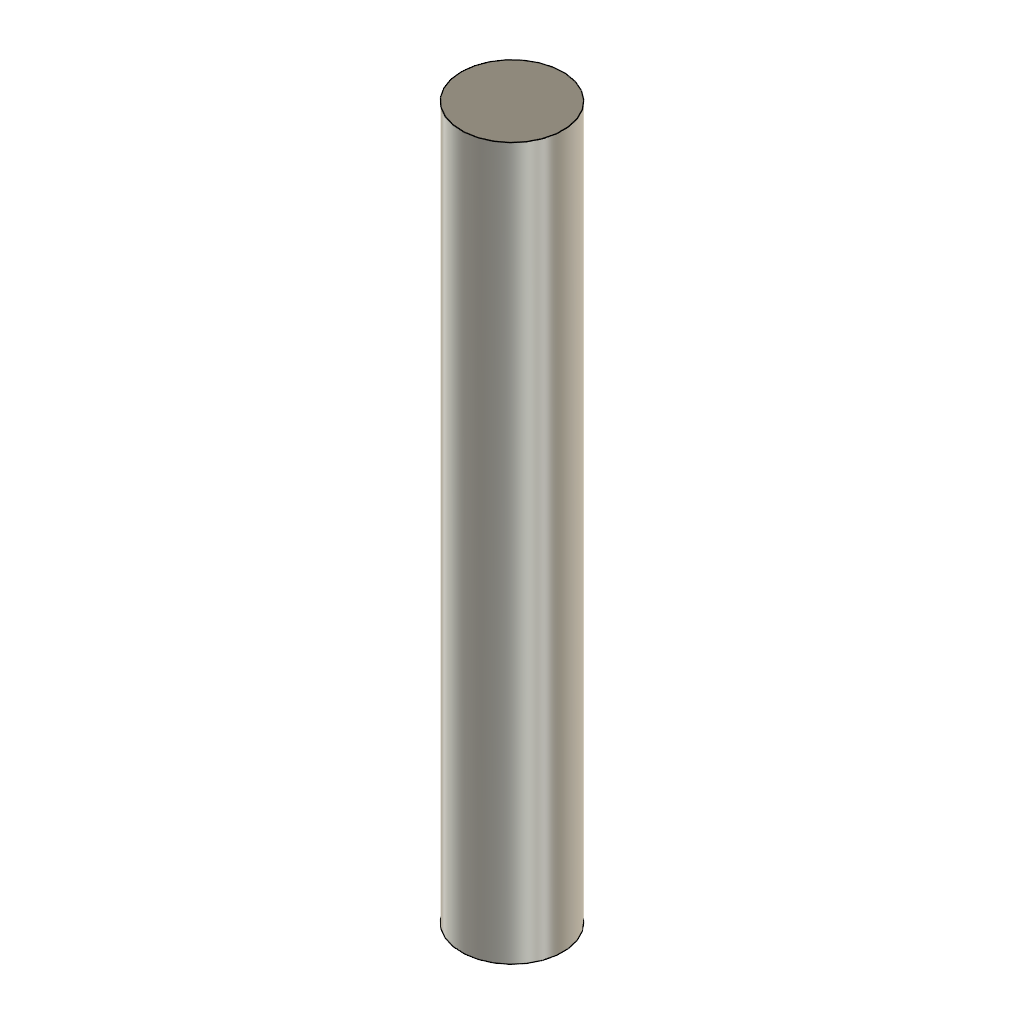
FLASH Core XY (Autodesk Fusion 360 archive; units mm, degrees)
design "Pulley Pin"
part number: 2026-10-21-10-58-50-393
Autodesk Fusion 360 part; units mm, degrees
sketch "Sketch1" plane through (0, 0, 0) normal (0, 0, 1) x (1, 0, 0)
  circle A0 centre (0, 0) radius 2.5
  dimension "d1" = 5
  constraint coincident A0.centre origin
  measures "d1" diameter of A0
extrude "Extrude1" add sketch "Sketch1" along normal mid plane 35

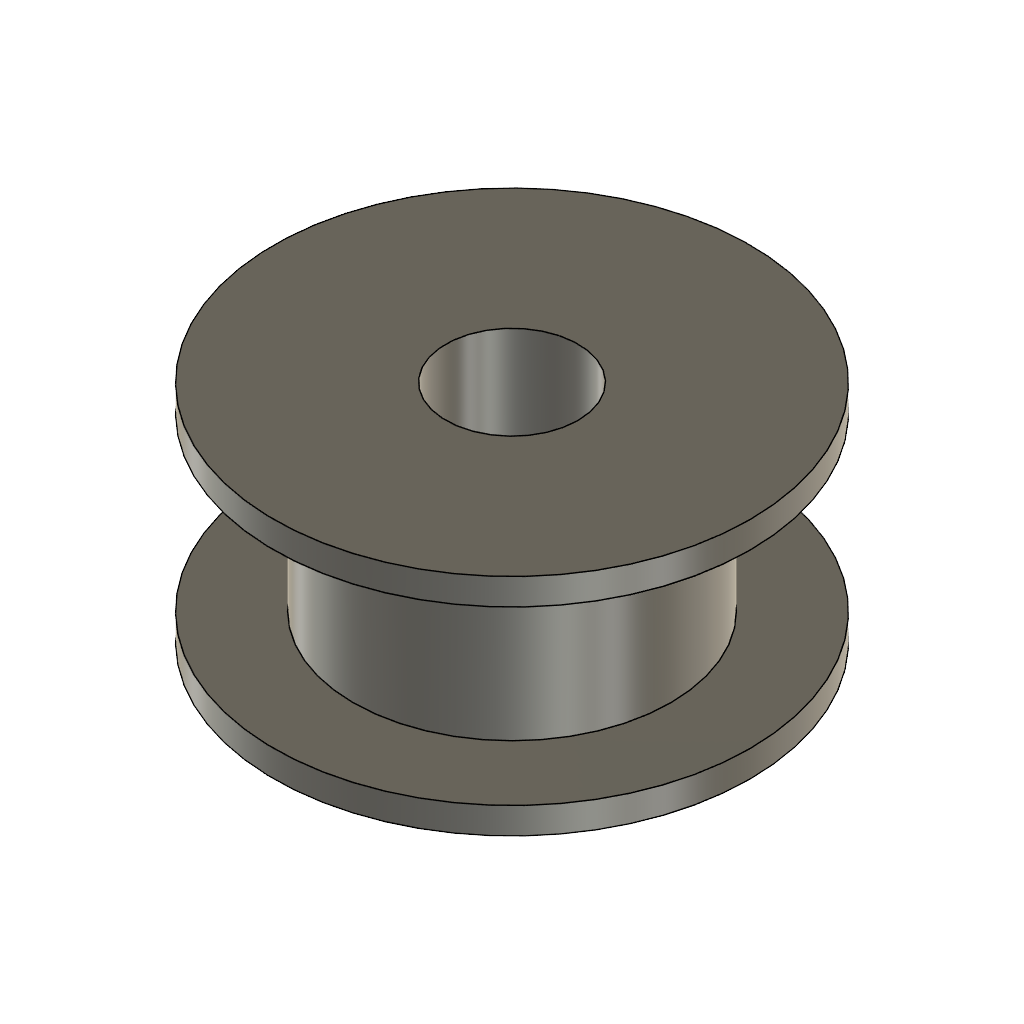
design "GT2 Idler Pulley 6mm"
part number: 2026-10-15-13-51-56-063
Autodesk Fusion 360 part; units mm, degrees
sketch "Sketch1" plane through (0, 0, 0) normal (0, 0, 1) x (1, 0, 0)
  circle A0 centre (0, 0) radius 6
  dimension "d1" = 12
  constraint coincident A0.centre origin
  measures "d1" diameter of A0
extrude "Extrude1" add sketch "Sketch1" along normal mid plane 6.5 makes body 1
sketch "Sketch2" plane through (0, 0, 3.25) normal (0, 0, 1) x (-1, 0, 0)
  circle A0 centre (0, 0) radius 6
  circle A1 centre (0, 0) radius 9
  dimension "d4" = 18
  constraint coincident A0.centre A1.centre
  measures "d4" diameter of A1
extrude "Extrude2" add sketch "Sketch2" along normal blind 1 contours A0 | A1 bodies 1
mirror "Mirror1" about plane through (0, 0, 0) normal (0, 0, 1) of "Extrude2"
sketch "Sketch3" plane through (0, 0, 4.25) normal (0, 0, 1) x (-1, 0, 0)
  circle A0 centre (0, 0) radius 9
hole "Hole1" at (0, 0, 4.25) direction (0, 0, -1) diameter 5 end through all bodies 1
sketch "Sketch4" plane through (0, 0, 0) normal (0, 0, 1) x (1, 0, 0)
  circle A0 centre (0, 0) radius 10
  dimension "d11" = 20
  constraint coincident A0.centre origin
  measures "d11" diameter of A0
extrude "Extrude3" add sketch "Sketch4" along normal mid plane 9.5 separate body makes body 2
hidden bodies 2
named bodies: "Pulley", "Pocket"

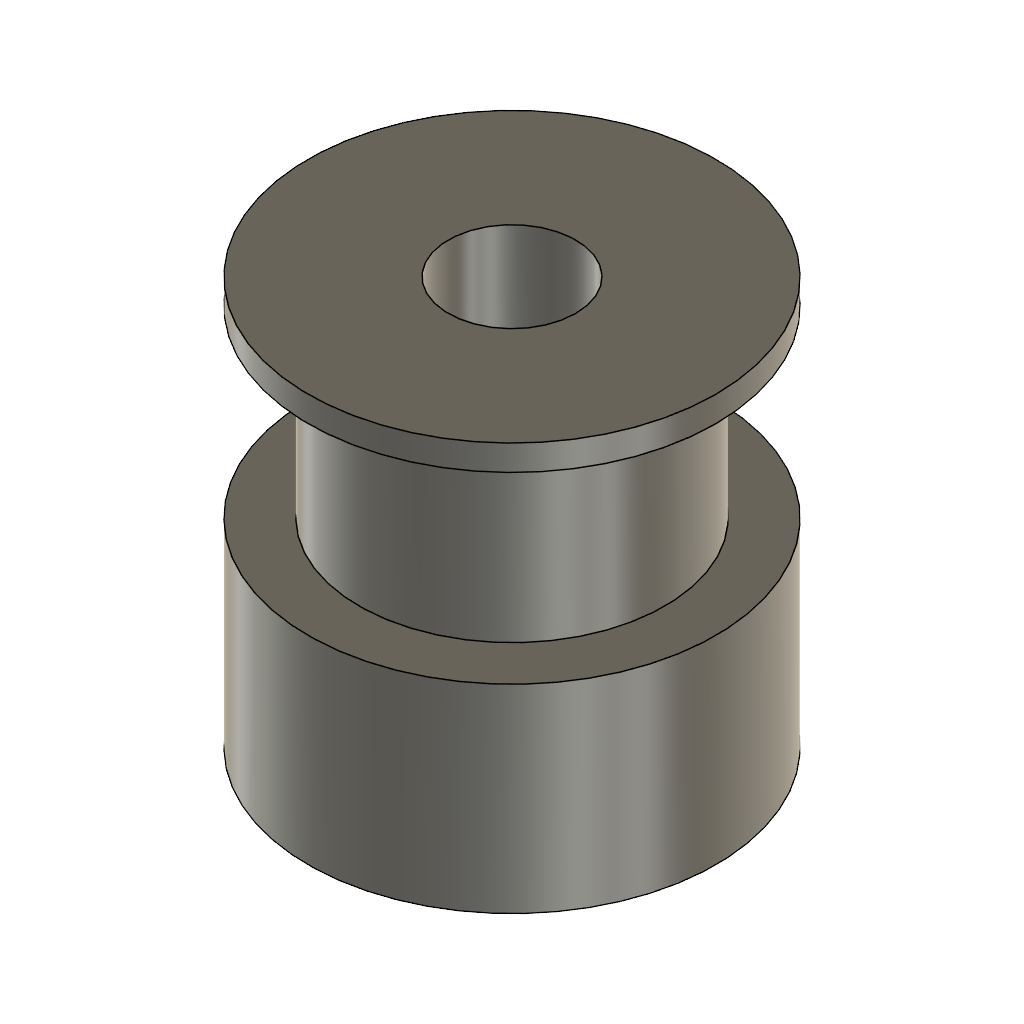
design "GT Drive Pulley 6mm"
part number: 2026-10-15-14-07-30-111
Autodesk Fusion 360 part; units mm, degrees
sketch "Sketch1" plane through (0, 0, 0) normal (0, 0, 1) x (1, 0, 0)
  circle A0 centre (0, 0) radius 6
  dimension "d1" = 12
  constraint coincident A0.centre origin
  measures "d1" diameter of A0
extrude "Extrude1" add sketch "Sketch1" along normal mid plane 7.2 makes body 1
sketch "Sketch2" plane through (0, 0, 3.6) normal (0, 0, 1) x (-1, 0, 0)
  circle A0 centre (0, 0) radius 6
  circle A1 centre (0, 0) radius 8
  dimension "d4" = 16
  constraint coincident A0.centre A1.centre
  measures "d4" diameter of A1
extrude "Extrude2" add sketch "Sketch2" along normal blind 1 contours A0 | A1 bodies 1
sketch "Sketch3" plane through (0, 0, -3.6) normal (0, 0, -1) x (1, 0, 0)
  circle A0 centre (0, 0) radius 6
  circle A1 centre (0, 0) radius 8
  dimension "d7" = 16
  constraint coincident A0.centre A1.centre
  measures "d7" diameter of A1
extrude "Extrude3" add sketch "Sketch3" along normal blind 7.8 contours A0 | A1 bodies 1
sketch "Sketch4" plane through (0, 0, 4.6) normal (0, 0, 1) x (-1, 0, 0)
  circle A0 centre (0, 0) radius 8
hole "Hole1" at (0, 0, 4.6) direction (0, 0, -1) diameter 5 end through all bodies 1
sketch "Sketch5" plane through (0, 0, 0) normal (0, 0, 1) x (1, 0, 0)
  circle A0 centre (0, 0) radius 9
  dimension "d12" = 18
  constraint coincident A0.centre origin
  measures "d12" diameter of A0
extrude "Extrude4" add sketch "Sketch5" along normal up to surface (5.6 mm away) and the other way up to surface (12.4 mm away) separate body makes body 2
hidden bodies 2
named bodies: "Pulley", "Pocket"

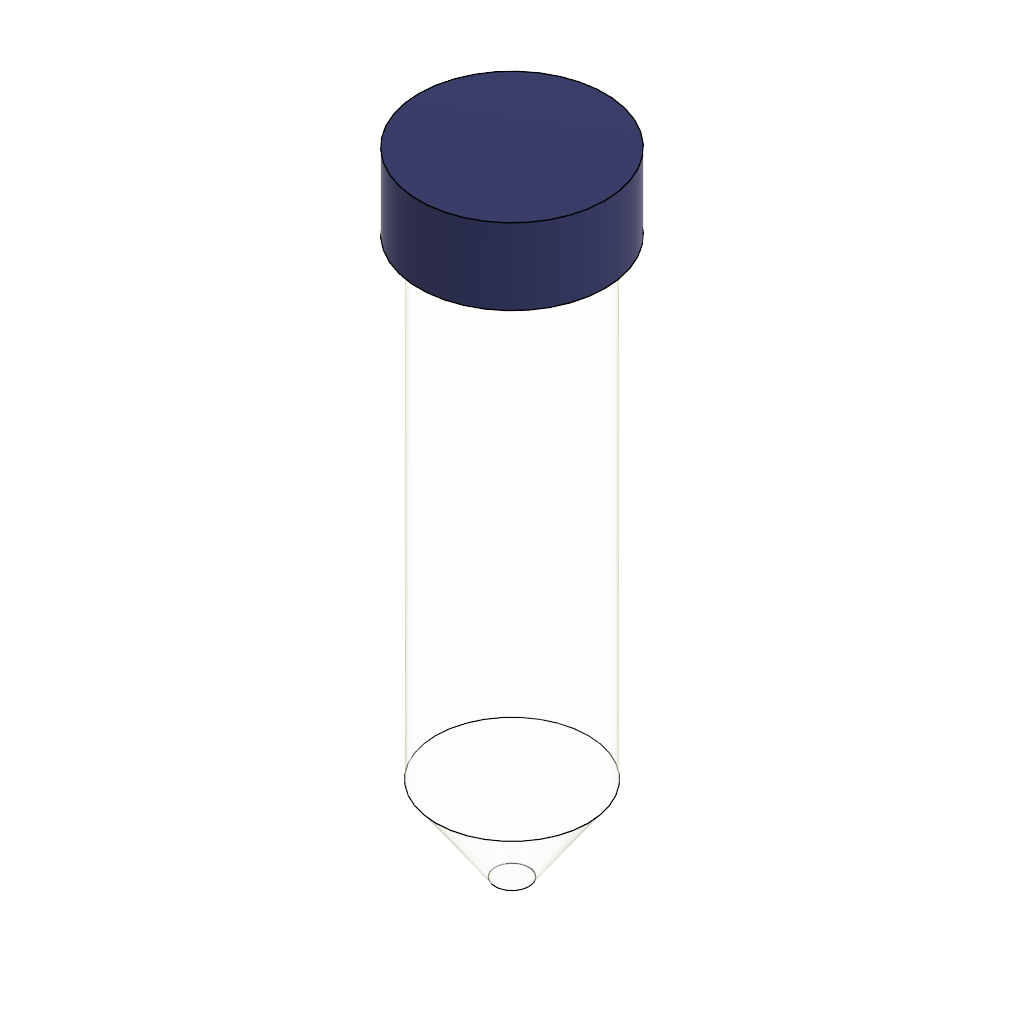
design "TestTube50mL"
Autodesk Fusion 360 part; units mm, degrees
sketch "Sketch1" plane through (0, 0, 0) normal (0, 0, 1) x (1, 0, 0)
  circle A0 centre (0, 0) radius 14.2875
  circle A1 centre (-150, 75) radius 3.1006
  dimension "d1" = 28.575
  constraint coincident A0.centre origin
  measures "d1" diameter of A0
extrude "Extrude1" add sketch "Sketch1" along normal blind 118.745 contours A0 makes body 1
sketch "Sketch2" plane through (0, 0, 118.745) normal (0, 0, 1) x (-1, 0, 0)
  circle A0 centre (0, 0) radius 14.2875
  circle A1 centre (0, 0) radius 17.4625
  dimension "d4" = 34.925
  constraint coincident A0.centre A1.centre
  measures "d4" diameter of A1
extrude "Extrude2" add sketch "Sketch2" against normal blind 14.2875 bodies 1
chamfer "Chamfer1" distance 15.875 distance2 11.1125 1 edges at (-13.3206, -5.1666, 0) measured on face at (14.2165, 1.4226, 69.6383) tangent chain off on bodies 1
ref_plane "WorkPlane1" through (0, 0, 20.6375) normal (0, 0, 1) x (1, 0, 0)
sketch "Sketch3" plane through (0, 0, 20.6375) normal (0, 0, 1) x (1, 0, 0)
  circle A0 centre (0, 0) radius 14.2875
  circle A1 centre (0, 0) radius 14.2875
split "Split1" by plane through (0, 0, 104.4575) normal (0, 0, -1) bodies 1 makes body 2 at (14.2165, 1.4226, 74.93)
equation "d5 = ( -9 / 16 ) * 1 in"
equation "d7 = ( 5 / 8 ) * 1 in"
equation "d8 = ( ( 1.125 - 0.25 ) / 2 ) * 1 in"
equation "d9 = ( 13 / 16 ) * 1 in"

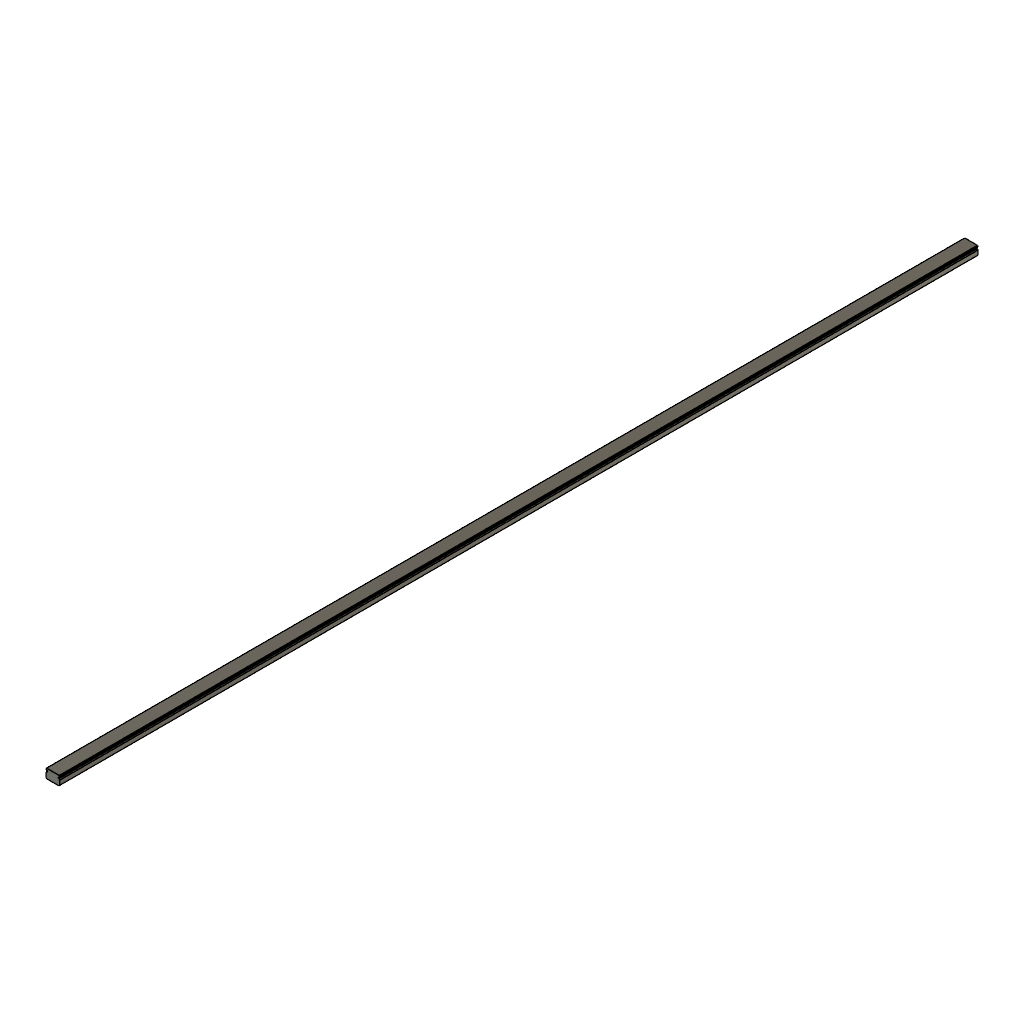
design "MGN15 Rail"
part number: 2026-10-15-13-23-19-019
Autodesk Fusion 360 part; units mm, degrees
sketch "Sketch1" plane through (0, 0, 0) normal (0, 1, 0) x (1, 0, 0)
  line L0 (-7.5, 0) -> (7.5, 0)
  line L1 (7.5, 0) -> (7.5, 10)
  line L2 (7.5, 10) -> (-7.5, 10)
  line L3 (-7.5, 10) -> (-7.5, 0)
  line L4 (-7.5, 0) -> (7.5, 10) construction
  line L5 (7.5, 0) -> (-7.5, 10) construction
  point P0 (0, 5)
  dimension "d1" = 15
  dimension "d2" = 10
  constraint horizontal L0
  constraint perpendicular L0 L1
  constraint parallel L0 L2
  constraint parallel L1 L3
  constraint coincident L4 P0
  constraint coincident L5 P0
  constraint vertical origin P0
  constraint coincident origin L0
  measures "d1" distance of L1.end L2.end
  measures "d2" distance of L0.start L2.end
extrude "Extrude1" add sketch "Sketch1" along normal mid plane 1000
sketch "Sketch2" plane through (0, 0, 0) normal (0, 1, 0) x (1, 0, 0)
  line L0 (-7.5, 0) -> (-7.5, 10)
  line L1 (-7.5, 10) -> (7.5, 10)
  line L2 (7.5, 10) -> (7.5, 0)
  line L3 (7.5, 0) -> (-7.5, 0)
  line L4 (7.5, 2.2) -> (5.8, 2.2)
  line L5 (5.8, 2.2) -> (5.8, 3.2)
  line L6 (5.8, 3.2) -> (7.5, 3.2)
  line L7 (7.5, 3.2) -> (7.5, 2.2)
  point P0 (5.8, 2.7)
  dimension "d5" = 7.3
  dimension "d6" = 1.7
  dimension "d7" = 1
  constraint horizontal L4
  constraint vertical L5
  constraint horizontal L6
  constraint vertical L7
  constraint coincident L2 L4.start
  constraint midpoint L5 P0
  measures "d5" distance of L1 P0
  measures "d6" distance of L5.end L6.end
  measures "d7" distance of L4.end L5.end
extrude "Extrude2" cut sketch "Sketch2" along normal through all and the other way through all contours L2 L4 L5 L6 L7
mirror "Mirror1" about plane through (0, 0, 0) normal (1, 0, 0) of "Extrude2"
chamfer "Chamfer1" distance 0.5 angle 45 2 edges at (-7.5, 0, 0) (7.5, 0, 0) tangent chain off
chamfer "Chamfer2" distance 0.9 angle 45 2 edges at (-7.5, 0, -10) (7.5, 0, -10) tangent chain off
chamfer "Chamfer3" distance 0.9 angle 45 4 edges at (-7.5, 0, -3.2) (-7.5, 0, -2.2) (7.5, 0, -3.2) (7.5, 0, -2.2) tangent chain off
fillet "Fillet1" radius 0.3 4 edges at (5.8, 0, -2.2) (5.8, 0, -3.2) (-5.8, 0, -2.2) (-5.8, 0, -3.2)

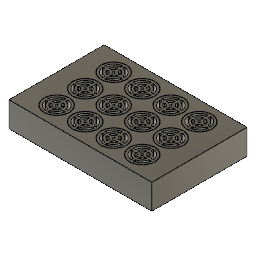
design "WellPlate3x4"
Autodesk Fusion 360 part; units mm, degrees
sketch "Sketch1" plane through (0, 0, 0) normal (0, 0, 1) x (1, 0, 0)
  line L0 (-63.75, 42.5) -> (63.75, 42.5)
  line L1 (63.75, 42.5) -> (63.75, -42.5)
  line L2 (63.75, -42.5) -> (-63.75, -42.5)
  line L3 (-63.75, -42.5) -> (-63.75, 42.5)
  line L4 (-63.75, 42.5) -> (63.75, -42.5) construction
  line L5 (63.75, 42.5) -> (-63.75, -42.5) construction
  dimension "d1" = 85
  dimension "d2" = 127.5
  constraint horizontal L0
  constraint perpendicular L0 L1
  constraint parallel L0 L2
  constraint parallel L1 L3
  constraint coincident L4 origin
  constraint coincident L5 origin
  measures "d1" distance of L0.start L2.end
  measures "d2" distance of L0.start L0.end
extrude "Extrude1" add sketch "Sketch1" along normal blind 22.5 makes body 1
sketch "Sketch2" plane through (0, 0, 22.5) normal (0, 0, 1) x (-1, 0, 0)
  line L0 (63.75, 42.5) -> (-63.75, 42.5)
  line L1 (-63.75, 42.5) -> (-63.75, -42.5)
  line L2 (-63.75, -42.5) -> (63.75, -42.5)
  line L3 (63.75, -42.5) -> (63.75, 42.5)
  circle A0 centre (38.1, -25.4) radius 11.25
  dimension "d5" = 22.5
  dimension "d6" = 38.1
  dimension "d7" = 25.4
  measures "d5" diameter of A0
  measures "d6" horizontal distance of origin A0.centre
  measures "d7" vertical distance of origin A0.centre
extrude "Extrude2" cut sketch "Sketch2" against normal through all contours A0 bodies 1
pattern_linear "R-Pattern1" count 4 spacing 25.4 along (1, 0, 0) count 3 spacing 25.4 along (0, -1, 0) of "Extrude2"
sketch "Sketch3" plane through (0, 0, 22.5) normal (0, 0, 1) x (-1, 0, 0)
  circle A0 centre (-38.1, 25.4) radius 11.25
  circle A1 centre (-12.7, 25.4) radius 11.25
  circle A2 centre (12.7, 25.4) radius 11.25
  circle A3 centre (38.1, 25.4) radius 11.25
  circle A4 centre (-38.1, 0) radius 11.25
  circle A5 centre (-12.7, 0) radius 11.25
  circle A6 centre (12.7, 0) radius 11.25
  circle A7 centre (38.1, 0) radius 11.25
  circle A8 centre (-38.1, -25.4) radius 11.25
  circle A9 centre (-12.7, -25.4) radius 11.25
  circle A10 centre (12.7, -25.4) radius 11.25
  circle A11 centre (38.1, -25.4) radius 11.25
  line L0 (63.75, 42.5) -> (-63.75, 42.5)
  line L1 (-63.75, 42.5) -> (-63.75, -42.5)
  line L2 (-63.75, -42.5) -> (63.75, -42.5)
  line L3 (63.75, -42.5) -> (63.75, 42.5)
  circle A12 centre (38.1, -25.4) radius 11.25
  circle A13 centre (38.1, -25.4) radius 1
  circle A14 centre (38.1, -25.4) radius 5
  circle A15 centre (38.1, -25.4) radius 7
  circle A16 centre (38.1, -25.4) radius 9
  circle A17 centre (38.1, -25.4) radius 3
  line L4 (26.85, -26.4) -> (49.35, -26.4)
  line L5 (49.35, -26.4) -> (49.35, -24.4)
  line L6 (49.35, -24.4) -> (26.85, -24.4)
  line L7 (26.85, -24.4) -> (26.85, -26.4)
  line L8 (26.85, -26.4) -> (49.35, -24.4) construction
  line L9 (49.35, -26.4) -> (26.85, -24.4) construction
  line L10 (37.1, -36.65) -> (39.1, -36.65)
  line L11 (39.1, -36.65) -> (39.1, -14.15)
  line L12 (39.1, -14.15) -> (37.1, -14.15)
  line L13 (37.1, -14.15) -> (37.1, -36.65)
  line L14 (37.1, -36.65) -> (39.1, -14.15) construction
  line L15 (39.1, -36.65) -> (37.1, -14.15) construction
  circle A18 centre (38.1, -25.4) radius 11
  point P0 (38.1, -25.4)
  point P1 (38.1, -25.4)
  dimension "d14" = 2
  dimension "d15" = 2
  dimension "d16" = 2
  dimension "d17" = 2
  dimension "d18" = 2
  dimension "d19" = 2
  dimension "d27" = 2
  dimension "d28" = 2
  constraint concentric A12 A13
  constraint concentric A12 A14
  constraint concentric A12 A15
  constraint concentric A14 A16
  constraint concentric A12 A17
  constraint horizontal L4
  constraint perpendicular L4 L5
  constraint parallel L4 L6
  constraint parallel L5 L7
  constraint coincident L8 P1
  constraint coincident L9 P1
  constraint coincident P1 P0
  constraint horizontal L10
  constraint perpendicular L10 L11
  constraint parallel L10 L12
  constraint parallel L11 L13
  constraint coincident L14 P1
  constraint coincident L15 P1
  constraint tangent A11 L7
  constraint tangent A12 L10
  constraint concentric A11 A18
  measures "d14" distance of A15 A16
  measures "d15" distance of A14 A15
  measures "d16" distance of A14 A17
  measures "d17" distance of A13 A17
  measures "d18" distance of L10.start L10.end
  measures "d19" distance of L4.end L5.end
  measures "d27" diameter of A13
  measures "d28" distance of A16 A18
extrude "Extrude3" add sketch "Sketch3" against normal blind 8 separate body contours A11 A12 L4 L6 A18 | A11 A12 L11 L13 A18 | A16 L4 L6 A18 | A16 L6 L11 A18 | A11 A12 L11 L13 A18 | A16 L4 L11 A18 | A16 L11 L13 A18 | A15 A16 L4 L6 | A16 L11 L13 A18 | A15 A16 L11 L13 | A16 L6 L13 A18 | A14 A15 L6 L11 | A14 A15 L4 L6 | A15 A16 L11 L13 | A16 L4 L13 A18 | A14 A15 L4 L11 | A11 A12 L4 L6 A18 | A14 A15 L11 L13 | A16 L4 L6 A18 | A14 A17 L4 L6 | A14 A15 L11 L13 | A15 A16 L4 L6 | A14 A15 L6 L13 | A14 A17 L11 L13 | A17 L6 L11 | A17 L4 L6 L11 | A14 A15 L4 L13 | A14 A17 L11 L13 | A17 L4 L11 | A14 A15 L4 L6 | A17 L6 L11 L13 | A13 L6 L11 | A17 L4 L11 L13 | A13 L4 L11 | A14 A17 L4 L6 | A17 L6 L13 | A13 L6 L13 | A17 L4 L13 | A13 L4 L13 | A17 L4 L6 L13 makes body 2
pattern_linear "R-Pattern2" count 3 spacing 25.4 along (0, -1, 0) count 4 spacing 25.4 along (1, 0, 0) of bodies 2 makes body 3 at (-47.8128, 0, 22.5) makes body 4 at (-47.8128, -25.4, 22.5) makes body 5 at (-22.4128, 25.4, 22.5) makes body 6 at (-22.4128, 0, 22.5) makes body 7 at (-22.4128, -25.4, 22.5) makes body 8 at (2.9872, 25.4, 22.5) makes body 9 at (2.9872, 0, 22.5) makes body 10 at (2.9872, -25.4, 22.5) makes body 11 at (28.3872, 25.4, 22.5) makes body 12 at (28.3872, 0, 22.5) makes body 13 at (28.3872, -25.4, 22.5)
shell "Shell1" thickness 2 removed faces 1 at (-58.95, 0, 0) on bodies 1
